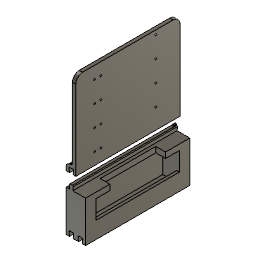
Coco_BladeContainer (Autodesk Fusion 360 design; units mm, degrees)
Autodesk Fusion 360 part; units mm, degrees
sketch "Sketch1" plane through (0, 0, 0) normal (1, 0, 0) x (0, 1, 0)
  line L0 (0, 0) -> (248.5, 0)
  line L1 (248.5, 0) -> (248.5, 34.55)
  line L2 (248.5, 34.55) -> (0, 34.55)
  line L3 (0, 34.55) -> (0, 0)
  line L4 (0, 34.55) -> (13.75, 34.55)
  line L5 (0, 14.05) -> (0, 34.55)
  line L6 (248.5, 34.55) -> (234.55, 34.55)
  line L7 (248.5, 14.05) -> (248.5, 34.55)
  line L8 (3.75, 30.8) -> (244.75, 30.8)
  line L9 (244.75, 30.8) -> (244.75, 3.75)
  line L10 (244.75, 3.75) -> (3.75, 3.75)
  line L11 (3.75, 3.75) -> (3.75, 30.8)
  line L12 (0, 34.55) -> (248.5, 34.55)
  line L13 (248.5, 34.55) -> (248.5, 30.8)
  line L14 (248.5, 30.8) -> (0, 30.8)
  line L15 (0, 30.8) -> (0, 34.55)
  dimension "d2" = 248.5
  dimension "d7" = 3.75
  dimension "d8" = 3.75
  dimension "d9" = 3.75
  dimension "d10" = 3.75
  dimension "d20" = 3.75
  constraint horizontal L0
  constraint vertical L1
  constraint horizontal L2
  constraint vertical L3
  constraint coincident L0.start L3.end
  constraint horizontal L4
  constraint vertical L5
  constraint horizontal L6
  constraint vertical L7
  constraint horizontal L8
  constraint vertical L9
  constraint horizontal L10
  constraint vertical L11
  constraint horizontal L12
  constraint vertical L13
  constraint horizontal L14
  constraint vertical L15
  constraint coincident L1 L13.end
  measures "d2" distance of L1.end L2.end
  measures "d7" distance of L2 L8
  measures "d8" distance of L0 L10
  measures "d9" distance of L1 L9
  measures "d10" distance of L3 L11
  measures "d20" distance of L12 L14
extrude "Extrude1" add sketch "Sketch1" along normal blind 20 contours L0 L1 L3 L5 L7 L9 L10 L11 L14 | L1 L2 L3 L4 L5 L6 L7 L8 L12 L13 L14 L15 makes body 1
extrude "Extrude2" add sketch "Sketch1" along normal blind 29 separate body contours L1 L2 L3 L4 L5 L6 L7 L8 L12 L13 L14 L15 makes body 2
ref_plane "WorkPlane1" through (14.5, 0, 32.675) normal (0, -1, 0) x (0, 0, -1)
sketch "Sketch4" plane through (0, 0, 0) normal (0, -1, 0) x (-1, 0, 0)
  line L0 (0, -34.55) -> (-29, -34.55)
  line L1 (-20, -34.55) -> (-20, 0)
  line L2 (-17, -41.55) -> (-20.5, -16.6462)
  line L3 (-20.5, -16.6462) -> (-24, -41.55)
  line L4 (-24, -41.55) -> (-17, -41.55)
  line L5 (-11, -41.55) -> (-4, -41.55)
  line L6 (-4, -41.55) -> (-7.5, -16.6462)
  line L7 (-7.5, -16.6462) -> (-11, -41.55)
  line L8 (-29, -34.55) -> (-29, -30.8)
  line L9 (0, 0) -> (0, -34.55)
  dimension "d43" = 7
  dimension "d46" = 7
  dimension "d51" = 7
  dimension "d52" = 4
  dimension "d56" = 6
  dimension "d63" = 82
  dimension "d64" = 82
  dimension "d65" = 82
  dimension "d66" = 82
  constraint parallel L0 L4
  measures "d43" horizontal distance of L2.start L3.end
  measures "d46" horizontal distance of L5.start L5.end
  measures "d51" distance of L0 L5
  measures "d52" horizontal distance of L0.start L5.end
  measures "d56" distance of L2.start L5.start
  measures "d63" angle of L5 L6
  measures "d64" angle of L5 L7
  measures "d65" angle of L2 L4
  measures "d66" angle of L3 L4
extrude "Extrude4" add sketch "Sketch4" against normal blind 150 contours L0 L5 L6 L7 | L0 L2 L3 L4 bodies 1 2
sketch "Sketch5" plane through (0, 150, 0) normal (0, 1, 0) x (-1, 0, 0)
  line L0 (-11, 41.55) -> (-10.0162, 34.55)
  line L1 (-10.0162, 34.55) -> (-4.9838, 34.55)
  line L2 (-4.9838, 34.55) -> (-4, 41.55)
  line L3 (-4, 41.55) -> (-11, 41.55)
  line L4 (-9, 41.55) -> (-6, 41.55)
  line L5 (-6, 41.55) -> (-6, 43.55)
  line L6 (-6, 43.55) -> (-9, 43.55)
  line L7 (-9, 43.55) -> (-9, 41.55)
  dimension "d57" = 3
  dimension "d59" = 2
  dimension "d140" = 2
  constraint horizontal L4
  constraint vertical L5
  constraint horizontal L6
  constraint vertical L7
  constraint coincident L3 L4.start
  measures "d57" distance of L5.end L6.end
  measures "d59" distance of L0.start L4.start
  measures "d140" distance of L4.end L5.end
extrude "Extrude5" add sketch "Sketch5" against normal blind 4 contours L3 L4 L5 L6 L7 bodies 1
sketch "Sketch8" plane through (0, 0, 0) normal (0, -1, 0) x (-1, 0, 0)
  line L0 (-0.0003, -49.9828) -> (-28.0003, -49.9828)
  line L1 (-28.0003, -49.9828) -> (-28.0003, -109.9828)
  line L2 (-28.0003, -109.9828) -> (-0.0003, -109.9828)
  line L3 (-0.0003, -109.9828) -> (-0.0003, -49.9828)
  dimension "d68" = 60
  dimension "d69" = 28
  constraint horizontal L0
  constraint vertical L1
  constraint horizontal L2
  constraint vertical L3
  measures "d68" distance of L0.start L2.end
  measures "d69" distance of L0.start L0.end
extrude "Extrude6" add sketch "Sketch8" against normal blind 150 separate body makes body 3
fillet "Fillet1" radius 1 4 edges at (4, 75, 41.55) (11, 75, 41.55) (17, 75, 41.55) (24, 75, 41.55) on bodies 1
fillet "Fillet1" radius 1 2 edges at (9, 148, 43.55) (6, 148, 43.55) on bodies 1
move_body "Move1" bodies 3 to x (1, 0, 0) y (0, 1, 0) z (0, 0, 1) at (0, 0, -16.233)
combine "Combine1" operation cut target body 3 tool bodies 1 keep tools
move_body "Move3" bodies 3 to x (1, 0, 0) y (0, 1, 0) z (0, 0, 1) at (0, 0, 40)
sketch "Sketch12" plane through (28.0003, 0, 0) normal (1, 0, 0) x (0, 1, 0)
  line L0 (0, 133.7498) -> (0, 74.55)
  line L1 (150, 74.55) -> (150, 133.7498)
  line L2 (150, 133.7498) -> (0, 133.7498)
  line L3 (15, 125.7498) -> (135, 125.7498)
  line L4 (135, 125.7498) -> (135, 98.7498)
  line L5 (135, 98.7498) -> (15, 98.7498)
  line L6 (15, 98.7498) -> (15, 125.7498)
  line L7 (35, 133.7498) -> (115, 133.7498)
  line L8 (115, 133.7498) -> (115, 125.7498)
  line L9 (115, 125.7498) -> (35, 125.7498)
  line L10 (35, 125.7498) -> (35, 133.7498)
  line L11 (0, 74.55) -> (150, 74.55)
  dimension "d89" = 120
  dimension "d90" = 15
  dimension "d91" = 27
  dimension "d92" = 8
  dimension "d93" = 80
  dimension "d275" = 20
  constraint horizontal L3
  constraint vertical L4
  constraint horizontal L5
  constraint vertical L6
  constraint horizontal L7
  constraint vertical L8
  constraint horizontal L9
  constraint vertical L10
  constraint coincident L3 L8.end
  constraint coincident L2 L7.start
  measures "d89" distance of L4.end L5.end
  measures "d90" distance of L1 L4
  measures "d91" distance of L3.start L5.end
  measures "d92" distance of L2 L3
  measures "d93" distance of L7.start L7.end
  measures "d275" distance of L3.end L8.end
extrude "Extrude8" cut sketch "Sketch12" against normal blind 24 contours L3 L4 L5 L6 L9 bodies 3
extrude "Extrude9" cut sketch "Sketch12" against normal blind 14 contours L2 L3 L7 L8 L9 L10 bodies 3
sketch "Sketch14" plane through (0, 0, 98.7498) normal (0, 0, 1) x (-1, 0, 0)
  line L0 (-28.0003, -15) -> (-28.0003, -135)
  line L1 (-28.0003, -135) -> (-4.0003, -135)
  line L2 (-4.0003, -135) -> (-4.0003, -15)
  line L3 (-4.0003, -15) -> (-28.0003, -15)
  line L4 (-4.0003, -15) -> (-24.0003, -15)
  line L5 (-24.0003, -15) -> (-24.0003, -135)
  line L6 (-24.0003, -135) -> (-4.0003, -135)
  line L7 (-4.0003, -135) -> (-4.0003, -15)
  dimension "d100" = 20
  constraint horizontal L4
  constraint vertical L5
  constraint horizontal L6
  constraint vertical L7
  constraint coincident L1 L5.end
  constraint coincident L2.end L3.start
  measures "d100" distance of L5.end L1.end
extrude "Extrude10" cut sketch "Sketch14" against normal blind 15 contours L1 L2 L3 L4 L5 L6 L7 bodies 3
sketch "Sketch17" plane through (0, 0, 0) normal (0, -1, 0) x (1, 0, 0)
  line L0 (28.0003, 74.55) -> (28.0003, 133.7498)
  line L1 (28.0003, 133.7498) -> (0.0003, 133.7498)
  line L2 (0.0003, 133.7498) -> (0.0003, 74.55)
  line L3 (0.0003, 74.55) -> (4.9838, 74.55)
  line L4 (4.9838, 74.55) -> (4.1601, 80.4108)
  arc A0 (5.1504, 81.55) -> (4.1601, 80.4108) centre (5.1504, 80.55) ccw
  line L5 (5.1504, 81.55) -> (9.8496, 81.55)
  arc A1 (10.8399, 80.4108) -> (9.8496, 81.55) centre (9.8496, 80.55) ccw
  line L6 (10.8399, 80.4108) -> (10.0162, 74.55)
  line L7 (10.0162, 74.55) -> (17.9838, 74.55)
  line L8 (17.9838, 74.55) -> (17.1601, 80.4108)
  arc A2 (18.1504, 81.55) -> (17.1601, 80.4108) centre (18.1504, 80.55) ccw
  line L9 (18.1504, 81.55) -> (22.8496, 81.55)
  arc A3 (23.8399, 80.4108) -> (22.8496, 81.55) centre (22.8496, 80.55) ccw
  line L10 (23.8399, 80.4108) -> (23.0162, 74.55)
  line L11 (23.0162, 74.55) -> (28.0003, 74.55)
  line L12 (4.0003, 140.7498) -> (7.3967, 116.5831)
  line L13 (7.3967, 116.5831) -> (10.7931, 140.7498)
  line L14 (10.7931, 140.7498) -> (4.0003, 140.7498)
  line L15 (-30.9525, 50.6679) -> (-39.5788, 50.6679)
  line L16 (-39.5788, 50.6679) -> (-39.5788, 44.0934)
  line L17 (-39.5788, 44.0934) -> (-30.9525, 44.0934)
  line L18 (-30.9525, 44.0934) -> (-30.9525, 50.6679)
  dimension "d117" = 82
  dimension "d118" = 82
  dimension "d119" = 7
  dimension "d120" = 4
  constraint horizontal L15
  constraint vertical L16
  constraint horizontal L17
  constraint vertical L18
  measures "d117" angle of L12 L14
  measures "d118" angle of L13 L14
  measures "d119" distance of L1 L14
  measures "d120" horizontal distance of L1.end L12.start
extrude "Extrude12" add sketch "Sketch17" against normal blind 150 contours L1 L12 L13 L14 bodies 3
ref_plane "WorkPlane4" through (14.0003, 75, 129.7498) normal (1, 0, 0) x (0, 0, -1)
sketch "Sketch16" plane through (14.0003, 0, 0) normal (1, 0, 0) x (0, 1, 0)
  line L0 (0, 249.8482) -> (150, 249.8482)
  line L1 (150, 249.8482) -> (150, 124.8482)
  line L2 (150, 124.8482) -> (0, 124.8482)
  line L3 (0, 124.8482) -> (0, 249.8482)
  dimension "d112" = 125
  dimension "d113" = 150
  constraint horizontal L0
  constraint vertical L1
  constraint horizontal L2
  constraint vertical L3
  measures "d112" distance of L0.start L2.end
  measures "d113" distance of L0.start L0.end
extrude "Extrude11" add sketch "Sketch16" against normal blind 14 separate body makes body 4
sketch "Sketch23" plane through (0, 150, 0) normal (0, 1, 0) x (-1, 0, 0)
  line L0 (-28.0003, 74.55) -> (-23.0162, 74.55)
  line L1 (-23.0162, 74.55) -> (-23.8399, 80.4108)
  arc A0 (-22.8496, 81.55) -> (-23.8399, 80.4108) centre (-22.8496, 80.55) ccw
  line L2 (-22.8496, 81.55) -> (-18.1504, 81.55)
  arc A1 (-17.1601, 80.4108) -> (-18.1504, 81.55) centre (-18.1504, 80.55) ccw
  line L3 (-17.1601, 80.4108) -> (-17.9838, 74.55)
  line L4 (-17.9838, 74.55) -> (-10.0162, 74.55)
  line L5 (-10.0162, 74.55) -> (-10.8399, 80.4108)
  arc A2 (-9.8496, 81.55) -> (-10.8399, 80.4108) centre (-9.8496, 80.55) ccw
  line L6 (-9.8496, 81.55) -> (-9, 81.55)
  arc A3 (-4.1601, 80.4108) -> (-5.1504, 81.55) centre (-5.1504, 80.55) ccw
  line L7 (-4.1601, 80.4108) -> (-4.9838, 74.55)
  line L8 (-4.9838, 74.55) -> (-0.0003, 74.55)
  line L9 (-0.0003, 74.55) -> (-0.0003, 133.7498)
  line L10 (-0.0003, 133.7498) -> (-4.9841, 133.7498)
  line L11 (-28.0003, 133.7498) -> (-28.0003, 74.55)
  line L12 (-8.7931, 140.7498) -> (-5.7931, 140.7498)
  line L13 (-5.7931, 140.7498) -> (-5.7931, 142.7498)
  line L14 (-5.7931, 142.7498) -> (-8.7931, 142.7498)
  line L15 (-8.7931, 142.7498) -> (-8.7931, 140.7498)
  line L16 (-9, 81.55) -> (-9, 82.55)
  arc A4 (-8, 83.55) -> (-9, 82.55) centre (-8, 82.55) ccw
  line L17 (-8, 83.55) -> (-7, 83.55)
  arc A5 (-6, 82.55) -> (-7, 83.55) centre (-7, 82.55) ccw
  line L18 (-6, 82.55) -> (-6, 81.55)
  line L19 (-6, 81.55) -> (-5.1504, 81.55)
  line L20 (-4.9841, 133.7498) -> (-4.0003, 140.7498)
  line L21 (-4.0003, 140.7498) -> (-10.7931, 140.7498)
  line L22 (-10.7931, 140.7498) -> (-9.8093, 133.7498)
  line L23 (-9.8093, 133.7498) -> (-28.0003, 133.7498)
  dimension "d141" = 3
  dimension "d142" = 2
  constraint horizontal L12
  constraint vertical L13
  constraint horizontal L14
  constraint vertical L15
  measures "d141" distance of L13.end L14.end
  measures "d142" distance of L12.end L13.end
extrude "Extrude16" add sketch "Sketch23" against normal blind 4 contours L12 L13 L14 L15 L21 bodies 3
fillet "Fillet3" radius 1 2 edges at (8.7931, 148, 142.7498) (5.7931, 148, 142.7498) on bodies 3
fillet "Fillet3" radius 1 2 edges at (4.0003, 75, 140.7498) (10.7931, 75, 140.7498) on bodies 3
move_body "Align4" bodies 4 to x (1, 0, 0) y (0, 1, 0) z (0, 0, 1) at (0, 0, 8.9016)
combine "Combine4" operation cut target body 4 tool bodies 3 keep tools
move_body "Move9" bodies 4 to x (1, 0, 0) y (0, 1, 0) z (0, 0, 1) at (0, 0, 20)
move_face "OffsetFaces7" offset -0.2 5 faces at (10.0839, 50, 135.7034) (8.7931, 147.3333, 141.4165) (23.5653, 100, 38.4572) (10.5653, 100, 38.4572) (9, 148.6667, 42.2167) on bodies 1 3
move_face "OffsetFaces8" offset -0.2 5 faces at (4.435, 50, 137.657) (5.7931, 148.6667, 141.0832) (17.7092, 100, 36.5036) (4.7092, 100, 36.5036) (6, 148.6667, 41.8833) on bodies 1 3
move_face "OffsetFaces9" offset -0.3 5 faces at (7.7955, 48.6667, 140.7498) (7.1931, 148.6667, 142.7498) (21.2159, 50, 41.55) (7.9333, 48.6667, 41.55) (7.4, 148.6667, 43.55) on bodies 1 3
sketch "Sketch38" plane through (14.0003, 0, 0) normal (1, 0, 0) x (0, 1, 0)
  line L0 (150, 278.7498) -> (0, 278.7498)
  line L1 (0, 278.7498) -> (0, 153.7498)
  line L2 (0, 153.7498) -> (150, 153.7498)
  line L3 (150, 153.7498) -> (150, 278.7498)
  point P0 (115, 182.7498)
  point P1 (27, 171.2498)
  point P2 (36, 171.2498)
  point P3 (115, 212.7498)
  point P4 (36, 201.2498)
  point P5 (27, 201.2498)
  point P6 (115, 242.7498)
  point P7 (36, 231.2498)
  point P8 (27, 231.2498)
  point P9 (115, 272.7498)
  point P10 (36, 261.2498)
  point P11 (27, 261.2498)
  dimension "d362" = 29
  dimension "d363" = 35
  dimension "d364" = 17.5
  dimension "d366" = 36
  dimension "d367" = 9
  dimension "d370" = 0
  dimension "d371" = 30
  measures "d362" distance of L2 P0
  measures "d363" distance of L3 P0
  measures "d364" distance of L2 P1
  measures "d366" distance of L1 P2
  measures "d367" distance of P1 P2
hole "Hole2" at (14.0003, 27, 171.2498) at (14.0003, 36, 171.2498) at (14.0003, 27, 201.2498) at (14.0003, 36, 201.2498) at (14.0003, 36, 231.2498) at (14.0003, 27, 231.2498) at (14.0003, 27, 261.2498) at (14.0003, 36, 261.2498) at (14.0003, 115, 272.7498) at (14.0003, 115, 242.7498) at (14.0003, 115, 212.7498) at (14.0003, 115, 182.7498) direction (-1, 0, 0) diameter 2.529 depth 20 tip angle 118 bodies 4
thread "Thread2" "ISO Metric profile 3.0 M3x0.5 6H" major diameter 3.086 minor diameter 2.529 pitch 0.5 angle 60 resizes the face on face at (9.3336, 113.7359, 212.7814) on face at (9.3336, 113.8474, 272.2298) on face at (9.3336, 26.0948, 260.3669) on face at (9.3336, 34.7359, 231.2814) on face at (9.3336, 25.7359, 201.2814) on face at (9.3336, 25.7359, 171.2814) on face at (9.3336, 34.7359, 171.2814) on face at (9.3336, 34.7359, 201.2814) on face at (9.3336, 25.7359, 231.2814) on face at (9.3336, 35.0948, 260.3669) on face at (9.3336, 113.7359, 242.7814) on face at (9.3336, 113.7359, 182.7814) on bodies 4
sketch "Sketch39" plane through (0.0003, 0, 0) normal (-1, 0, 0) x (0, -1, 0)
  circle A0 centre (-115, 212.7498) radius 1.2645
  circle A1 centre (-27, 261.2498) radius 1.2645
  circle A2 centre (-36, 231.2498) radius 1.2645
  circle A3 centre (-27, 201.2498) radius 1.2645
  circle A4 centre (-27, 171.2498) radius 1.2645
  circle A5 centre (-36, 171.2498) radius 1.2645
  circle A6 centre (-36, 201.2498) radius 1.2645
  circle A7 centre (-27, 231.2498) radius 1.2645
  circle A8 centre (-36, 261.2498) radius 1.2645
  circle A9 centre (-115, 242.7498) radius 1.2645
  circle A10 centre (-115, 182.7498) radius 1.2645
  line L0 (-150, 278.7498) -> (-150, 153.7498)
  line L1 (-150, 153.7498) -> (0, 153.7498)
  line L2 (0, 153.7498) -> (0, 278.7498)
  line L3 (-160, 290) -> (17.6558, 290)
  line L4 (17.6558, 290) -> (17.6558, 164.729)
  line L5 (17.6558, 164.729) -> (-160, 164.729)
  line L6 (-160, 164.729) -> (-160, 290)
  line L7 (0, 278.7498) -> (-150, 278.7498)
  circle A11 centre (-115, 272.7498) radius 1.2645
  constraint horizontal L3
  constraint vertical L4
  constraint horizontal L5
  constraint vertical L6
extrude "Extrude42" cut sketch "Sketch39" against normal blind 9 contours L0 L2 L5 L7 | L0 L2 L3 L4 L5 L6 L7 bodies 4
fillet "Fillet4" radius 10 1 edges at (11.5003, 0, 278.7498) on bodies 4
fillet "Fillet4" radius 10 1 edges at (11.5003, 150, 278.7498) on bodies 4
fillet "Fillet4" radius 2.5 1 edges at (9.0003, 75, 164.729) on bodies 4
fillet "Fillet4" radius 5 1 edges at (0.0003, 75, 164.729) on bodies 4
delete_body "RemoveBody1" bodies 1
equation "d2 = LengthVacuumBed"
equation "LengthVacuumBed = 248.5 mm"
equation "HeightVacuumBed = 27 mm"
named bodies: "EjectionTray", "StorageBody"
